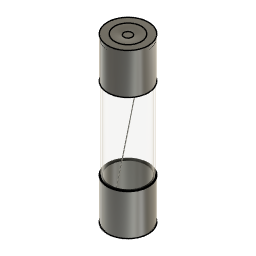
fuse (Autodesk Fusion 360 design; units mm, degrees)
Autodesk Fusion 360 part; units mm, degrees
sketch "Sketch1" plane through (0, 0, 0) normal (0, 0, 1) x (1, 0, 0)
  circle A0 centre (0, 0) radius 2.5
  dimension "d1" = 5
  constraint coincident A0.centre origin
  measures "d1" diameter of A0
extrude "Extrude1" add sketch "Sketch1" along normal blind 5 makes body 1
shell "Shell1" thickness 0.1 removed faces 1 at (-0.7508, 0.3616, 5) on bodies 1
sketch "Sketch3" plane through (0, 0, 0) normal (0, 0, 1) x (1, 0, 0)
  circle A0 centre (0, 0) radius 0.5
  dimension "d8" = 1
  constraint coincident A0.centre origin
  measures "d8" diameter of A0
extrude "Extrude3" cut sketch "Sketch3" along normal blind 0.05 bodies 1
sketch "Sketch6" plane through (0, 0, 0) normal (0, 1, 0) x (1, 0, 0)
  line L0 (-1.9972, -0.0014) -> (1.982, -19.4991)
pipe "Pipe2" add diameter 0.1 path "Sketch6" along L0 separate body makes body 2
sketch "Sketch7" plane through (0, 0, 5) normal (0, 0, 1) x (-1, 0, 0)
  circle A0 centre (0, 0) radius 2.4
  circle A1 centre (0, 0) radius 2.5
  circle A2 centre (0, 0) radius 2.25
  dimension "d27" = 4.5
  constraint concentric A0 A2
  measures "d27" diameter of A2
extrude "Extrude5" add sketch "Sketch7" along normal blind 10 separate body contours A0 makes body 3
sketch "Sketch8" plane through (0, 0, 15) normal (0, 0, 1) x (-1, 0, 0)
  circle A0 centre (0, 0) radius 2.25
  circle A1 centre (0, 0) radius 2.4
  circle A2 centre (0, 0) radius 2.5
  dimension "d30" = 5
  constraint concentric A0 A2
  measures "d30" diameter of A2
extrude "Extrude6" add sketch "Sketch8" along normal blind 5 separate body contours A2 makes body 4
sketch "Sketch9" plane through (0, 0, 20) normal (0, 0, 1) x (-1, 0, 0)
  circle A0 centre (0, 0) radius 2.4
  circle A1 centre (0, 0) radius 2.5
  circle A2 centre (0, 0) radius 2.5
  dimension "d33" = 5
  constraint coincident A0.centre A1.centre
  measures "d33" diameter of A2
extrude "Extrude7" add sketch "Sketch9" against normal blind 0.5 contours A0 bodies 2 4
extrude "Extrude9" cut 1 faces at (0.3557, -0.1033, 0.05) along direction (0, 0, 1) blind 0.1 on bodies 1 bodies 1
sketch "Sketch10" plane through (0, 0, 0.1) normal (0, 0, 1) x (-1, 0, 0)
  circle A0 centre (0, 0) radius 2.4
  circle A1 centre (0, 0) radius 0.5
sketch "Sketch11" plane through (0, 0, 20) normal (0, 0, 1) x (-1, 0, 0)
  circle A0 centre (0, 0) radius 2.5
  circle A1 centre (0, 0) radius 0.5
  dimension "d44" = 1
  constraint concentric A0 A1
  measures "d44" diameter of A1
extrude "Extrude11" cut sketch "Sketch11" against normal blind 0.1 contours A1 bodies 2
fillet "Fillet3" radius 6.5 1 edges at (0.4662, -0.1808, 20) on bodies 2
sketch "Sketch13" plane through (0, 0, 0.1) normal (0, 0, 1) x (-1, 0, 0)
  circle A0 centre (0, 0) radius 0.5
  circle A1 centre (0, 0) radius 2.4
  circle A2 centre (0, 0) radius 0.75
  dimension "d51" = 1.5
  constraint concentric A0 A2
  measures "d51" diameter of A2
extrude "Extrude12" add sketch "Sketch13" along normal blind 0.2 separate body contours A0 | A2 makes body 5
fillet "Fillet4" radius 6.5 1 edges at (-0.4662, -0.1808, 0) on bodies 1
